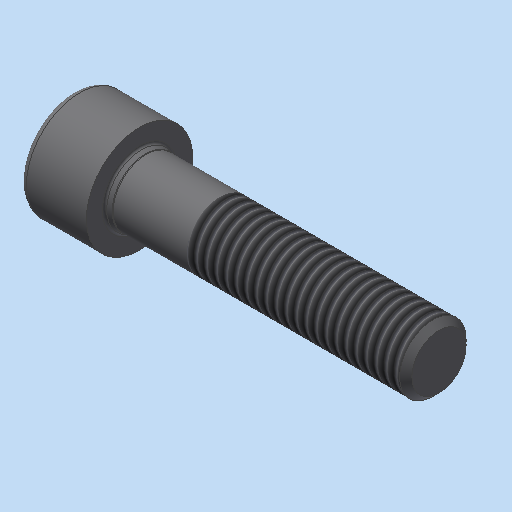
# Autodesk Inventor part: Zylinderschraube_ISO_4762___M10x45
Saved by Autodesk Inventor 2023.3 (Build 273359000, 359)
## iProperties
Shininess: 64.0
Length Units: 11269
Angle Units: 11279
Time Units: 11290
Mass Units: 11283
Length Display Precision: 3
Angle Display Precision: 2
Compacted: True
Part Number: Zylinderschraube_ISO_4762___M10x45
Document SubType Name: Modeling
Created: 2004-04-03
Material: xStahl_AnP_Dummymaterial
Description: =<RBPARTNOTITLE2>
Vendor: NORM8
Designer: S.Riedelsheimer
Manufacturer: Standard
Standards Organization: Custom
Density: 7.85 g/cm^3
Appearance: Stahl - normal AnP
Mass: 40.4559 g
Surface Area: 24.3658 cm^2
Volume: 5.15362 cm^3
Density: 0.0
Volumn: 0.0
Area: 0.0
PropertySet Name: Model Information
Control State: 0
Master: False
Checked Out: False
CNS_NB: Zylinderschraube ISO 4762 - M10x45
CNS_NN: ISO 4762
CNS_NT: Zylinderschrauben mit Innensechskant
CNS_NBSYN: Zylinderschraube ISO 4762 - $NENN.
CNS_LINA: Zylinderschraube ISO 4762 - M10x45
CNS_D: 10.000
CNS_D3: 8.160
CNS_P: 1.500
CNS_L: 45.000
CNS_S: 8.000
CNS_HM: 32.000
CNS_DK: 16.000
CNS_DA: 11.200
CNS_DS: 10.000
CNS_E: 9.150
CNS_K: 10.000
CNS_R: 0.400
CNS_T: 5.000
CNS_V: 1.000
CNS_DW: 15.330
CNS_W: 4.000
CNS_LF: 1.020
CNS_LG: 13.000
CNS_FORM: 0.000
CNS_NENN: M10x45
CNS_KT: DUMMY
PSOL_IDENT_0: {C:\partsolutions8\data\23d-libs\bosch_bamberg\schrauben\zylinderschrauben\din_en_iso_4762.prj},171
PSOL_IDENT_1: {M=Nenngewinde},{VTYP=3D},{NB=Zylinderschraube ISO 4762 - M10x45},{NN=ISO 4762},{DATE=26.11.2003},{G
PSOL_IDENT_2: EOMDATE=26.11.2003},{VERSION=v2},{LINEID=900},{LINESUBID=-1},{WBVAR=}  {NB=Zylinderschraube ISO 4762
PSOL_IDENT_3: - M10x45},{LINA=Zylinderschraube ISO 4762 - M10x45},{KT=DUMMY},{IDNR=},{D=10.000},{D3=8.160},{P=1.5
PSOL_IDENT_4: 00},{L=45.000},{S=8.000},{HM=32.000},{DK=16.000},{DA=11.200},{DS=10.000},{E=9.150},{K=10.000},{R=0.4
PSOL_IDENT_5: 00},{T=5.000},{V=1.000},{DW=15.330},{W=4.000},{LF=1.020},{LG=13.000},{FORM=0.000},{NENN=M10x45}
RBPARTNOTITLE2: Zylinderschrauben mit Innensechskant
RBPARTNOTITLE1: Hexagon socket head cap screws
AnP_Kategorie: 4
RBDRAWINGMISSINGSPEC: --
RBPARTMADEOF: ISO 4762 - M10x45 - 8.8 verzinkt
Title: Zylinderschraube ISO 4762 - M10x45
Author: S.Riedelsheimer
Keywords: =<RBPARTMADEOF>
Comments: =<RBSURFACE2>
Revision Number: 01
Autodesk Inventor part; units mm, degrees
sketch "Sketch_1" plane through (0, 0, 0) normal (0, 1, 0) x (-1, 0, 0)
  line L0 (-48, 0) -> (13, 0)
  line L1 (1.6906, 0) -> (4, -4)
  line L2 (4, -4) -> (9.425, -4)
  line L3 (9.425, -4) -> (10, -4.575)
  line L4 (10, -4.575) -> (10, -7)
  arc A0 (9, -8) -> (10, -7) centre (9, -7) ccw
  line L5 (9, -8) -> (0, -8)
  line L6 (0, -8) -> (0, -5.6)
  arc A1 (0, -5.6) -> (-0.2772, -5.2193) centre (-0.4, -5.6) ccw
  line L7 (-0.2772, -5.2193) -> (-0.8972, -5.0193)
  arc A2 (-0.8972, -5.0193) -> (-1.02, -5) centre (-1.02, -5.4) ccw
  line L8 (-1.02, -5) -> (-44.08, -5)
  line L9 (-44.08, -5) -> (-45, -4.08)
  line L10 (-45, -4.08) -> (-45, 0)
  line L11 (-45, 0) -> (1.6906, 0)
  constraints: 24 end point, 6 point on circle, 3 centre point
revolve "Drehung1" add sketch "Sketch_1" angle 360 about axis through (48, 0, 0) along (1, 0, 0)
thread "Gewinde1" size "M10x1.5" class "6g" standard "ANSI Metric M Profile" length 32
sketch "Skizze_1" plane through (-4, 0, 0) normal (1, 0, 0) x (0, 0, -1)
  line L0 (-4, 2.3094) -> (-4, -2.3094)
  line L1 (-4, -2.3094) -> (0, -4.6188)
  line L2 (0, -4.6188) -> (4, -2.3094)
  line L3 (4, -2.3094) -> (4, 2.3094)
  line L4 (4, 2.3094) -> (0, 4.6188)
  line L5 (0, 4.6188) -> (-4, 2.3094)
  constraints: 12 end point
extrude "Extrusion1" cut sketch "Skizze_1" against normal blind 10
ref_plane "IP1_XY" through (0, 0, 0) normal (1, 0, 0) x (0, 0, -1)
ref_plane "IP1_YZ" through (0, 0, 0) normal (0, 0, -1) x (0, 1, 0)
ref_plane "IP3_XY" through (45, 0, 0) normal (1, 0, 0) x (0, 0, -1)
ref_plane "IP3_YZ" through (45, 0, 0) normal (0, 0, -1) x (0, 1, 0)
ref_plane "IP2_XY" through (-10, 0, 0) normal (1, 0, 0) x (0, 0, -1)
ref_plane "IP2_YZ" through (-10, 0, 0) normal (0, 0, -1) x (0, 1, 0)
